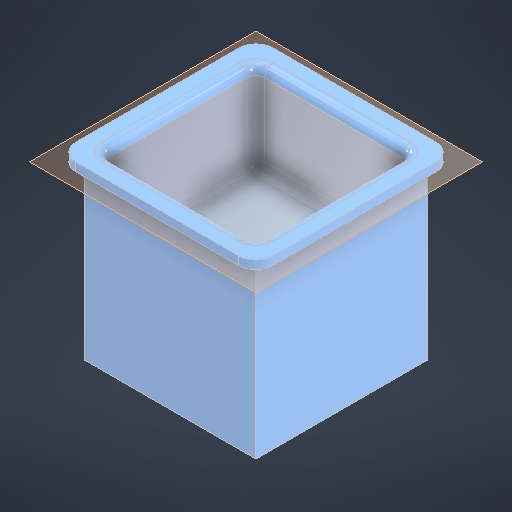
# Autodesk Inventor part: 2_05_recipien_eau
Saved by Autodesk Inventor 2026 (Build 300175000, 175)
## iProperties
Created: 2025-05-08
Part Number: 2_05_recipien_eau
Material: Gummi
Document SubType Name: Modeling
Designer: karle
Density: 0.93 g/cm^3
Appearance: Gummi - Schwarz
Author: karle
Autodesk Inventor part; units mm, degrees
ref_plane "YZ Plane" through (0, 0, 0) normal (1, 0, 0) x (0, 1, 0)
ref_plane "XZ Plane" through (0, 0, 0) normal (0, 1, 0) x (-1, 0, 0)
ref_plane "XY Plane" through (0, 0, 0) normal (0, 0, 1) x (1, 0, 0)
ref_plane "Arbeitsebene1" through (0, 0, 0) normal (0, 0, 1) x (1, 0, 0)
sketch "Skizze1" plane through (0, 0, 0) normal (0, 0, 1) x (1, 0, 0)
  line L0 (-50, 50) -> (50, 50)
  line L1 (50, 50) -> (50, -50)
  line L2 (50, -50) -> (-50, -50)
  line L3 (-50, -50) -> (-50, 50)
  point P0 (0, 0)
  dimension "d0" = 100
  dimension "d1" = 100
  dimension "d2" = 50
  dimension "d3" = 50
  constraints: 8 end point, 2 parallel, 1 horizontal, 1 perpendicular
  measures "d0" distance between parallel lines of L3 L1
  measures "d1" distance between parallel lines of L2 L0
  measures "d2" distance from line of point (0, 0) L1
  measures "d3" distance from line of point (0, 0) L0
extrude "Extrusion1" add sketch "Skizze1" against normal blind 100
sketch "Skizze3" plane through (0, 0, 0) normal (0, 0, 1) x (1, 0, 0)
  line L0 (-57.5, 57.5) -> (57.5, 57.5)
  line L1 (57.5, 57.5) -> (57.5, -57.5)
  line L2 (57.5, -57.5) -> (-57.5, -57.5)
  line L3 (-57.5, -57.5) -> (-57.5, 57.5)
  point P0 (0, 0)
  dimension "d12" = 115
  dimension "d13" = 115
  dimension "d14" = 57.5
  dimension "d15" = 57.5
  constraints: 8 end point, 2 parallel, 1 horizontal, 1 perpendicular
  measures "d12" distance of L0.start L0.end
  measures "d13" distance of L2.end L0.start
  measures "d14" distance from line of point (0, 0) L0
  measures "d15" distance from line of point (0, 0) L3
extrude "Extrusion3" add sketch "Skizze3" along normal blind 5
sketch "Skizze2" plane through (0, 0, 0) normal (0, 0, 1) x (1, 0, 0)
  line L0 (-45, 45) -> (45, 45)
  line L1 (45, 45) -> (45, -45)
  line L2 (45, -45) -> (-45, -45)
  line L3 (-45, -45) -> (-45, 45)
  point P0 (0, 0)
  dimension "d6" = 90
  dimension "d7" = 90
  dimension "d8" = 45
  dimension "d9" = 45
  constraints: 8 end point, 2 parallel, 1 horizontal, 1 perpendicular
  measures "d6" distance of L0.end L1.end
  measures "d7" distance between parallel lines of L1 L3
  measures "d8" distance from line of L1 point (0, 0)
  measures "d9" distance from line of point (0, 0) L2
extrude "Extrusion2" cut sketch "Skizze2" along normal mid plane 95
fillet "Rundung1" radius 10 4 edges at (57.5, -57.5, 2.5) (-57.5, -57.5, 2.5) (-57.5, 57.5, 2.5) (57.5, 57.5, 2.5)
fillet "Rundung2" radius 5 12 edges at (45, 45, -21.25) (0, 45, -47.5) (45, 0, -47.5) (-45, 45, -21.25) (-45, 0, -47.5) (-45, -45, -21.25) (0, -45, -47.5) (45, -45, -21.25) (0, -45, 5) (45, 0, 5) (0, 45, 5) (-45, 0, 5)
